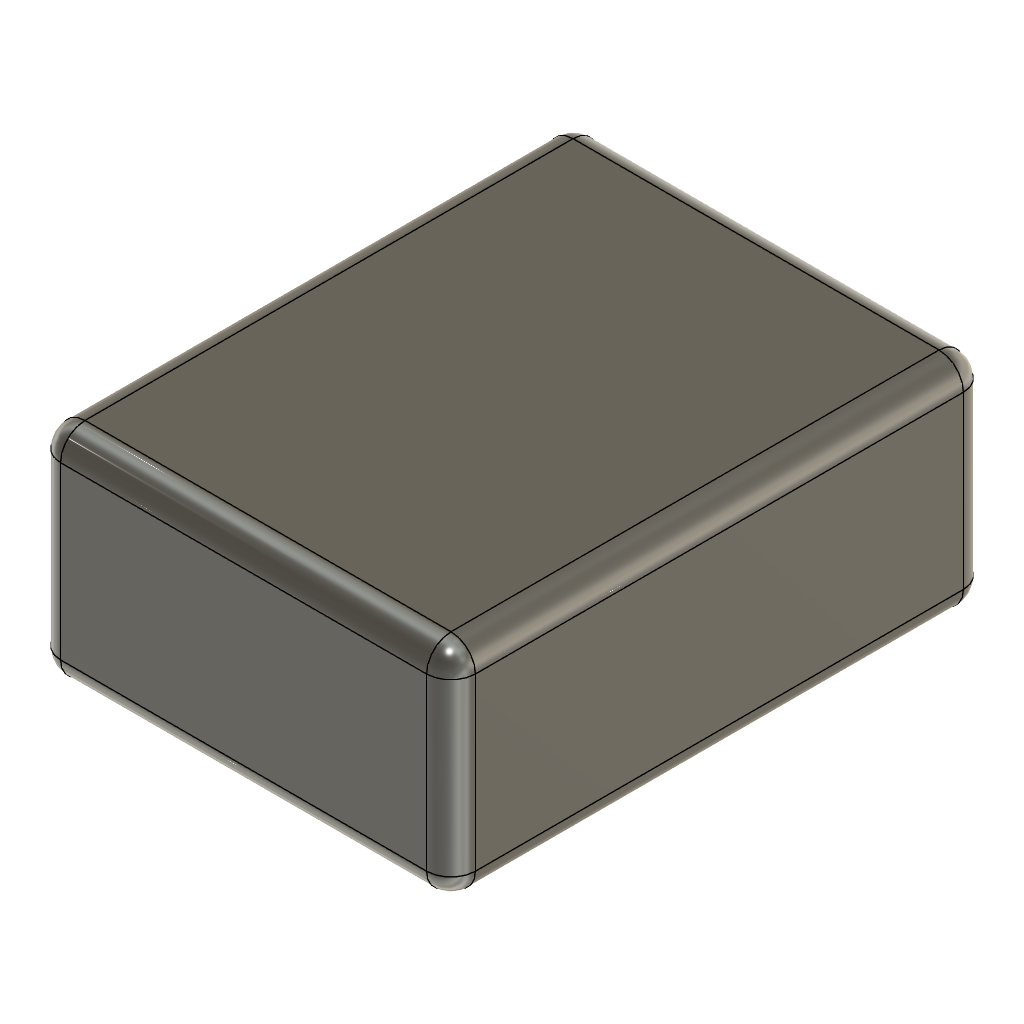
Battery (Autodesk Fusion 360 design; units mm, degrees)
part number: 2026-09-30-19-18-57-149
Autodesk Fusion 360 part; units mm, degrees
sketch "Szkic1" plane through (0, 0, 0) normal (0, 0, 1) x (1, 0, 0)
  line L0 (0, 0) -> (17, 0)
  line L1 (17, 0) -> (17, 22)
  line L2 (17, 22) -> (0, 22)
  line L3 (0, 22) -> (0, 0)
  constraint horizontal L0
  constraint vertical L1
  constraint horizontal L2
  constraint vertical L3
  constraint coincident L0.start L3.end
extrude "Wyciągnięcie proste1" add sketch "Szkic1" along normal blind 9
fillet "Zaokrąglenie1" radius 1 1 edges at (17, 0, 4.5)
fillet "Zaokrąglenie2" radius 1 1 edges at (0, 0, 4.5)
fillet "Zaokrąglenie3" radius 1 1 edges at (17, 22, 4.5)
fillet "Zaokrąglenie4" radius 1 1 edges at (0, 22, 4.5)
fillet "Zaokrąglenie5" radius 1 8 edges at (16.7071, 21.7071, 9) (8.5, 22, 9) (0.2929, 21.7071, 9) (0, 11, 9) (0.2929, 0.2929, 9) (8.5, 0, 9) (16.7071, 0.2929, 9) (17, 11, 9)
fillet "Zaokrąglenie6" radius 1 8 edges at (8.5, 22, 0) (0.2929, 21.7071, 0) (0, 11, 0) (0.2929, 0.2929, 0) (8.5, 0, 0) (16.7071, 0.2929, 0) (17, 11, 0) (16.7071, 21.7071, 0)
